Autodesk Fusion 360 part; units mm, degrees
(part 18 of 18)
